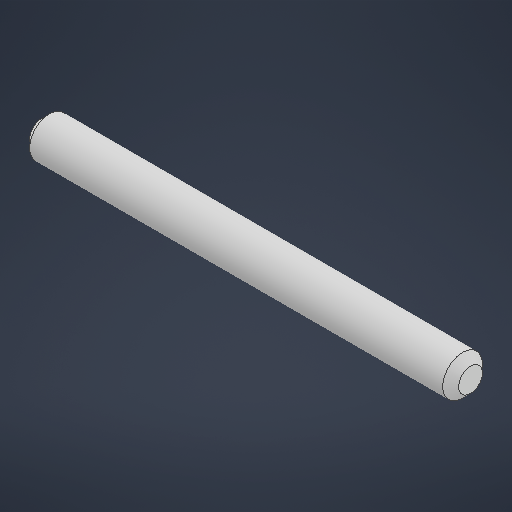
# Autodesk Inventor part: Pecinha maios simples1
Saved by Autodesk Inventor 2026.2 (Build 302298000, 298)
## iProperties
Created: 2026-08-28
Part Number: Pecinha maios simples1
Material: Genérico
Document SubType Name: Modeling
Designer: IFSP
Density: 1 g/cm^3
Appearance: Padrão
Author: IFSP
Autodesk Inventor part; units mm, degrees
ref_plane "YZ Plane" through (0, 0, 0) normal (1, 0, 0) x (0, 1, 0)
ref_plane "XZ Plane" through (0, 0, 0) normal (0, 1, 0) x (-1, 0, 0)
ref_plane "XY Plane" through (0, 0, 0) normal (0, 0, 1) x (1, 0, 0)
sketch "Esboço1" plane through (0, 0, 0) normal (0, 0, 1) x (1, 0, 0)
  line L0 (0, 0) -> (-54, 0)
  line L1 (-54, 0) -> (-54, 2.5)
  line L2 (-54, 2.5) -> (0, 2.5)
  line L3 (0, 2.5) -> (0, 0)
  dimension "d0" = 54
  dimension "d1" = 2.5
  constraints: 8 end point, 2 perpendicular, 1 horizontal, 1 vertical
  measures "d0" distance of L0.start L0.end
  measures "d1" distance of L0.end L1.end
revolve "Revolução1" add sketch "Esboço1" angle 360 about axis through (0, 0, 0) along (-1, 0, 0)
chamfer "Chanfro1" distance 1 angle 45 1 edges at (0, -2.5, 0) measured on face at (0, -0.7379, 0.3873)
chamfer "Chanfro2" distance 1 angle 45 1 edges at (-54, -2.5, 0) measured on face at (-54, 1.2612, 0.6619)
